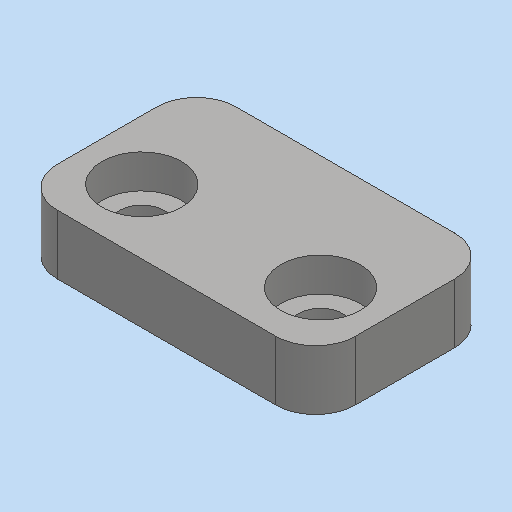
# Autodesk Inventor part: MM0948AN160_G01_106
Saved by Autodesk Inventor 2023.3 (Build 273359000, 359)
## iProperties
RuleStatus: InUse
Part Number: MM0948AN160_G01_106
Material: 1.2842 90MnCrV8
Description: =<RBPARTNOTITLE2>
Document SubType Name: Modeling
Designer: ric7an
Mass: 19.375 g
Surface Area: 17.7722 cm^2
Volume: 2.46815 cm^3
Density: 7.85 g/cm^3
Appearance: Stahl - normal AnP
Created: 2023-03-23
BeforeDocSave0: file://AnP_Ansicht_ausrichten
RBDOCUMENTTYPE: DRF
RBDOCUMENTVERSION: 00
RBDRAWINGMAINSCALE: 1:1
RBDRAWINGMISSINGSPEC: --
RBDRAWINGVOLUME: --
RBGBEDGESIN1: +0,5
RBGBEDGESIN2: +0,2
RBGBEDGESOUT1: -0,3
RBGBEDGESOUT2: -0,1
RBMATERIAL: =<Material>
RBMATMEETS: --
RBMATNO: =<Part Number>
RBPARTMADEOF: 6 x 18 x 30 (FM)
RBPARTNO: SIEHE MNR
RBPARTNOTITLE1: manufactured part
RBPARTNOTITLE2: Anfertigungsteil
RBPARTSAFETYINDICATOR: --
RBSURFACE: chemically nickel-coated
RBSURFACE2: chem. vernickelt
RBZEDGESNORM: ISO13715:2002-06
RBZGENDIMCLASS: m
RBZGENDIMNORM: ISO 2768-1:1989-11
RBZGENGEOCLASS: H
RBZGENGEONORM: ISO 2768-2:1989-11
RBZSURFACENORM: ISO13D2:2002-02
RBZTOLERANCENORM: ISO 14405-1:2010-12
AnP_Material: =<Material>
AnP_TemplVers: 20190222
AnP_Kategorie: 1
MaxAbmaße: 6 x 18 x 30 (FM)
AnP_Kommentar_aktuell: =<Comments>
AnP_Material_aktuell: =<Material>
Author: FH/Wi
Keywords: =<RBPARTMADEOF>
Comments: =<RBSURFACE2>
Revision Number: 01
Autodesk Inventor part; units mm, degrees
ref_plane "YZ Plane" through (0, 0, 0) normal (1, 0, 0) x (0, 1, 0)
ref_plane "XZ Plane" through (0, 0, 0) normal (0, 1, 0) x (-1, 0, 0)
ref_plane "XY Plane" through (0, 0, 0) normal (0, 0, 1) x (1, 0, 0)
sketch "Skizze1" plane through (0, 0, 0) normal (0, 0, 1) x (1, 0, 0)
  line L0 (-15, 18) -> (15, 18)
  line L1 (15, 18) -> (15, 0)
  line L2 (15, 0) -> (-15, 0)
  line L3 (-15, 0) -> (-15, 18)
  line L4 (0, 21.6) -> (0, -3.6) projected
  line L5 (-21, 0) -> (21, 0) projected
  point P0 (0, 0)
  dimension "d0" = 18
  dimension "d1" = 30
  constraints: 8 end point, 2 parallel, 1 collinear, 1 horizontal, 1 perpendicular, 1 other
  measures "d0" distance of L0.end L1.end
  measures "d1" distance of L0.start L0.end
extrude "Extrusion1" add sketch "Skizze1" along normal blind 6
sketch "Skizze2" plane through (0, 0, 0) normal (0, 0, -1) x (-1, 0, 0)
  circle A0 centre (0, 26) radius 15.25
  line L0 (0, -8.25) -> (0, 49.5) projected
  line L1 (-21.35, 0) -> (21.35, 0) projected
  line L2 (15, 18) -> (-15, 18) projected
  point P0 (0, 0)
  dimension "d4" = 8
  dimension "d5" = 30.5
  constraints: 1 centre point, 1 point on line
  measures "d4" distance from line of L2 A0.centre
  measures "d5" diameter of A0
extrude "Extrusion2" cut sketch "Skizze2" against normal blind 2
fillet "Rundung1" radius 4 4 edges at (-15, 0, 3) (15, 0, 3) (15, 18, 3) (-15, 18, 3)
sketch "Skizze3" plane through (0, 0, 6) normal (0, 0, 1) x (1, 0, 0)
  line L0 (0, 21.6) -> (0, -3.6) projected
  line L1 (-21, 0) -> (21, 0) projected
  point P0 (0, 0)
  point P1 (9, 6.5)
  point P2 (-9, 6.5)
  dimension "d9" = 6.5
  dimension "d18" = 18
  constraints: 1 symmetric about line
  measures "d9" distance from line of L1 point (9, 6.5)
  measures "d18" distance of point (9, 6.5) point (-9, 6.5)
hole "Bohrung1" at (9, 6.5, 6) at (-9, 6.5, 6) direction (0, 0, -1) diameter 4.5 end through all counterbore diameter 8 counterbore depth 3.4 clearance for "Flachk.Schr. DIN 6912  versenkt" size "M4" standard "ISO"
